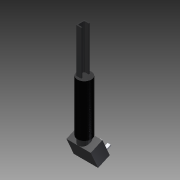
# Autodesk Inventor part: collective
Saved by Autodesk Inventor 2015 (Build 190159000, 159)
## iProperties
Created: 2022-11-07
Part Number: collective
Material: Generic
Document SubType Name: Modeling
Designer: Pavel Brodský
Density: 1 g/cm^3
Appearance: Default
Author: Pavel Brodský
Autodesk Inventor part; units mm, degrees
ref_plane "YZ Plane" through (0, 0, 0) normal (1, 0, 0) x (0, 1, 0)
ref_plane "XZ Plane" through (0, 0, 0) normal (0, 1, 0) x (-1, 0, 0)
ref_plane "XY Plane" through (0, 0, 0) normal (0, 0, 1) x (1, 0, 0)
sketch "Náčrt1" plane through (0, 0, 0) normal (0, 0, 1) x (1, 0, 0)
  line L0 (0, 0) -> (-15, 0)
  line L1 (-18, -3) -> (-18, -25)
  line L2 (-15, -28) -> (0, -28)
  line L3 (0, -28) -> (0, -24.5)
  line L4 (0, -24.5) -> (-11.5, -24.5)
  line L5 (-14.5, -21.5) -> (-14.5, -6.5)
  line L6 (-11.5, -3.5) -> (0, -3.5)
  line L7 (0, -3.5) -> (0, 0)
  arc A0 (-18, -25) -> (-15, -28) centre (-15, -25) ccw
  arc A1 (-14.5, -21.5) -> (-11.5, -24.5) centre (-11.5, -21.5) ccw
  arc A2 (-11.5, -3.5) -> (-14.5, -6.5) centre (-11.5, -6.5) ccw
  arc A3 (-15, 0) -> (-18, -3) centre (-15, -3) ccw
  point P0 (-18, 0)
  point P1 (-18, -28)
  dimension "d0" = 3.5
  dimension "d1" = 3.5
  dimension "d2" = 3.5
  dimension "d3" = 28
  dimension "d4" = 18
  dimension "d5" = 3
  constraints: 16 end point, 8 point on circle, 8 tangent, 5 perpendicular, 5 point on line, 4 centre point, 3 equal radius, 1 horizontal, 1 parallel, 1 vertical
  measures "d0" distance between parallel lines of L1 L5
  measures "d1" distance between parallel lines of L0 L6
  measures "d2" distance between parallel lines of L2 L4
  measures "d3" distance of point (-18, 0) point (-18, -28)
  measures "d4" distance of point (-18, -28) L2.end
  measures "d5" radius of A0
extrude "Vysunutí1" add sketch "Náčrt1" along normal blind 145
sketch "Náčrt2" plane through (-14.5, -21.5, 0) normal (1, 0, 0) x (0, 0, -1)
  circle A0 centre (-115, 7.5) radius 4
  line L0 (-145, 0) -> (-145, 15) projected
  line L1 (0, 21.5) -> (-145, 21.5) projected
  line L2 (0, -6.5) -> (-145, -6.5) projected
  dimension "d8" = 8
  dimension "d9" = 30
  dimension "d10" = 14
  dimension "d11" = 28
  constraints: 1 centre point
  measures "d8" diameter of A0
  measures "d9" distance from line of L0 A0.centre
  measures "d10" distance from line of L1 A0.centre
  measures "d11" distance between parallel lines of L2 L1
extrude "Vysunutí2" cut sketch "Náčrt2" against normal blind 145
sketch "Náčrt3" plane through (0, 0, 0) normal (0, 0, -1) x (-1, 0, 0)
  circle A0 centre (3.5, -14) radius 23
  line L0 (15, -28) -> (0, -28) projected
  point P0 (0, 0)
  dimension "d14" = 46
  dimension "d15" = 14
  dimension "d16" = 28
  dimension "d17" = 3.5
  constraints: 1 centre point
  measures "d14" diameter of A0
  measures "d15" vertical distance of point (0, 0) A0.centre
  measures "d16" distance from line of L0 point (0, 0)
  measures "d17" horizontal distance of point (0, 0) A0.centre
extrude "Vysunutí3" add sketch "Náčrt3" along normal blind 170
sketch "Náčrt4" plane through (-3.5, -14, -170) normal (0, 0, -1) x (-1, 0, 0)
  circle A0 centre (0, 0) radius 19
  point P0 (-3.5, 14)
  dimension "d20" = 38
  constraints: 1 centre point
  measures "d20" diameter of A0
extrude "Vysunutí4" add sketch "Náčrt4" along normal blind 21
sketch "Náčrt5" plane through (-14.5, -21.5, 145) normal (1, 0, 0) x (0, 0, -1)
  line L0 (336, -11.5) -> (336, 26.5) projected
  line L1 (336, -12.2415) -> (314.5471, 35.9424)
  line L2 (314.5471, 35.9424) -> (336, 35.9424)
  point P0 (145, 21.5)
  dimension "d23" = 24
  constraints: 4 end point, 2 point on line, 1 horizontal
  measures "d23" angle of L1 L0
extrude "Vysunutí5" cut sketch "Náčrt5" along normal through all both and the other way through all fills toward (325.3193, 11.8707) open curves L1 L2
sketch "Náčrt6" plane through (-3.5, -14, -182.2105) normal (0, 0.4067366, -0.9135455) x (-1, 0, 0)
  line L0 (-40, 21.0934) -> (40, 21.0934)
  line L1 (40, 21.0934) -> (40, -20.9066)
  line L2 (40, -20.9066) -> (-40, -20.9066)
  line L3 (-40, -20.9066) -> (-40, 21.0934)
  ellipse E0 centre (0, 0) end of major axis (0, -20.7981) minor radius 19 projected
  line L4 (0, 21.0934) -> (0, -20.9066) construction
  point P0 (-3.5, 86.9013)
  dimension "d28" = 80
  dimension "d29" = 42
  constraints: 10 end point, 2 midpoint, 2 parallel, 1 horizontal, 1 perpendicular, 1 point on line, 1 other
  measures "d28" distance of L0.start L0.end
  measures "d29" distance of L0.end L1.end
extrude "Vysunutí6" add sketch "Náčrt6" along normal blind 60
sketch "Náčrt7" plane through (-43.5, 5.2697, -173.6311) normal (0, 0.9135455, 0.4067366) x (1, 0, 0)
  circle A0 centre (10.3409, 47.5417) radius 7.0086
  circle A1 centre (10.3409, 47.5417) radius 5.1374
  circle A2 centre (10.3409, 26.4831) radius 7.0086
  circle A3 centre (10.3409, 26.4831) radius 5.1374
  circle A4 centre (37.1427, 27.9189) radius 7.0086
  circle A5 centre (37.1427, 27.9189) radius 5.1374
  circle A6 centre (58.2013, 27.9189) radius 7.0086
  circle A7 centre (58.2013, 27.9189) radius 5.1374
  line L0 (34.2711, 55.3588) -> (42.2801, 55.3588)
  line L1 (42.2801, 55.3588) -> (42.2801, 50.2537)
  line L2 (42.2801, 50.2537) -> (34.2711, 50.2537)
  line L3 (34.2711, 50.2537) -> (34.2711, 55.3588)
  line L4 (58.2013, 55.3588) -> (68.4115, 55.3588)
  line L5 (68.4115, 55.3588) -> (68.4115, 50.2537)
  line L6 (68.4115, 50.2537) -> (58.2013, 50.2537)
  line L7 (58.2013, 50.2537) -> (58.2013, 55.3588)
  point P0 (43.5, -160.7633)
  constraints: 16 end point, 8 centre point, 4 coincident, 4 parallel, 2 horizontal, 2 perpendicular, 2 point on line, 1 horizontal alignment
extrude "Vysunutí7" add sketch "Náčrt7" along normal blind 8 contours A0 | A2
extrude "Vysunutí8" add sketch "Náčrt7" along normal blind 10 contours A1 | A3
extrude "Vysunutí9" add sketch "Náčrt7" along normal blind 20 contours L0 L1 L2 L3 | L4 L5 L6 L7
extrude "Vysunutí10" add sketch "Náčrt7" along normal blind 6 contours A5 | A7
equation "\"d1\" = d0"
equation "\"d2\" = d0"
equation "\"d10\" = 0.5 * d11"
equation "\"d15\" = 0.5 * d16"
